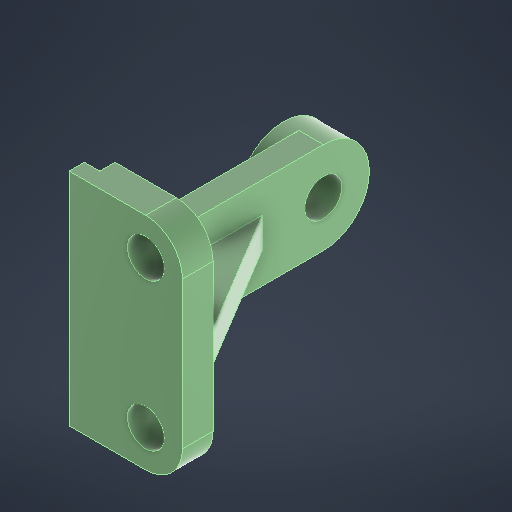
# Autodesk Inventor part: Bracket
Saved by Autodesk Inventor 2026.3 (Build 303398000, 398)
## iProperties
Created: 2026-11-02
Part Number: Bracket
Material: Iron, Gray
Document SubType Name: Modeling
Designer: ADMIN
Density: 7.15 g/cm^3
Appearance: Smooth - Dark Forest Green
Author: ADMIN
Autodesk Inventor part; units mm, degrees
ref_plane "YZ Plane" through (0, 0, 0) normal (1, 0, 0) x (0, 1, 0)
ref_plane "XZ Plane" through (0, 0, 0) normal (0, 1, 0) x (-1, 0, 0)
ref_plane "XY Plane" through (0, 0, 0) normal (0, 0, 1) x (1, 0, 0)
sketch "Sketch1" plane through (0, 0, 0) normal (0, 1, 0) x (-1, 0, 0)
  line L0 (0, -5) -> (0, 0)
  line L1 (0, 0) -> (-37, 0)
  line L2 (-37, 0) -> (-37, -10)
  line L3 (-37, -10) -> (-5, -10)
  line L4 (-5, -10) -> (-5, -5)
  line L5 (-5, -5) -> (0, -5)
  dimension "d0" = 5
  dimension "d1" = 10
  dimension "d2" = 37
  dimension "d3" = 5
  constraints: 12 end point, 5 perpendicular, 1 coincident, 1 vertical
  measures "d0" distance of L0.start L0.end
  measures "d1" distance of L1.end L2.end
  measures "d2" distance of L0.end L1.end
  measures "d3" distance of L4.end L0.start
extrude "Extrusion1" add sketch "Sketch1" along normal mid plane 72
sketch "Sketch2" plane through (5, -36, -5) normal (-1, 0, 0) x (0, 0, 1)
  line L0 (-5, 0) -> (-5, 72) projected
  line L1 (-5, 36) -> (-65, 36) construction
  arc A0 (-65, 51) -> (-65, 21) centre (-65, 36) ccw
  line L2 (-65, 51) -> (-5, 51)
  line L3 (-65, 21) -> (-5, 21)
  point P0 (5, 36)
  dimension "d6" = 60
  dimension "d7" = 30
  constraints: 6 end point, 2 perpendicular, 2 point on circle, 2 point on line, 2 tangent, 1 centre point, 1 coincident, 1 horizontal, 1 midpoint
  measures "d6" distance of L1.start L1.end
  measures "d7" diameter of A0
extrude "Extrusion2" add sketch "Sketch2" against normal blind 8
sketch "Sketch3" plane through (5, -36, -5) normal (-1, 0, 0) x (0, 0, 1)
  arc A0 (-65, 51) -> (-65, 21) centre (-65, 36) ccw projected
  circle A1 centre (-65, 36) radius 15
  point P0 (5, 36)
  dimension "d10" = 30
  constraints: 1 centre point, 1 coincident
  measures "d10" diameter of A1
extrude "Extrusion3" add sketch "Sketch3" along normal blind 5
sketch "Sketch4" plane through (13, -36, -5) normal (1, 0, 0) x (0, 0, -1)
  arc A0 (65, 21) -> (65, 51) centre (65, 36) ccw projected
  point P0 (-5, 36)
  constraints: 1 coincident
hole "Hole1" at (13, 0, -70) direction (-1, 0, 0) diameter 12 end through all
sketch "Sketch5" plane through (0, 0, 0) normal (0, 1, 0) x (-1, 0, 0)
  line L0 (-37, -10) -> (-37, 0) projected
  line L1 (-13, -10) -> (-37, -10)
  line L2 (-37, -10) -> (-13, -50)
  line L3 (-13, -10) -> (-13, -70) projected
  point P0 (0, 0)
  dimension "d20" = 40
  constraints: 4 end point, 1 perpendicular, 1 point on line
  measures "d20" vertical distance of L0.start L2.end
extrude "Extrusion4" add sketch "Sketch5" along normal mid plane 10
fillet "Fillet1" radius 15 2 edges at (9, 15, -10) (9, -15, -10)
fillet "Fillet2" radius 12 2 edges at (37, 36, -5) (37, -36, -5)
sketch "Sketch6" plane through (37, 5, -10) normal (0, 0, -1) x (-1, 0, 0)
  arc A0 (12, 31) -> (0, 19) centre (12, 19) ccw projected
  arc A1 (0, -29) -> (12, -41) centre (12, -29) ccw projected
  point P0 (37, -5)
  constraints: 2 coincident
hole "Hole2" at (25, 24, -10) at (25, -24, -10) direction (0, 0, 1) diameter 12 end through all
body "Solid1"
